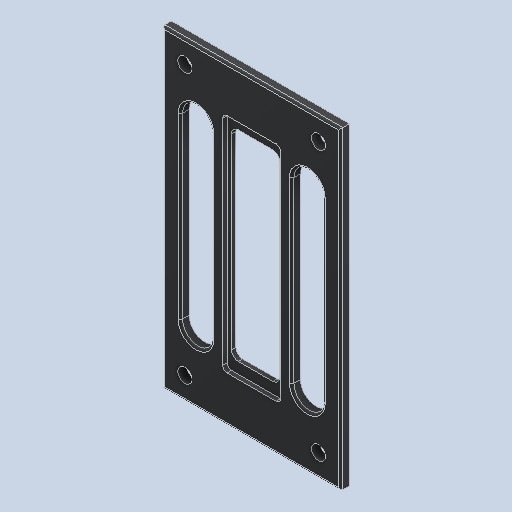
# Autodesk Inventor part: Cabezal camara
Saved by Autodesk Inventor 2025.3 (Build 293356000, 356)
## iProperties
Created: 2026-11-25
Part Number: Cabezal camara
Material: PLA (ácido poliláctico) - FDM nominal
Document SubType Name: Modeling
Designer: STEVEN LONDOÑO
Density: 1.24 g/cm^3
Appearance: PLA negro mate - capas FDM
Author: STEVEN LONDOÑO
Autodesk Inventor part; units mm, degrees
ref_plane "YZ Plane" through (0, 0, 0) normal (1, 0, 0) x (0, 1, 0)
ref_plane "XZ Plane" through (0, 0, 0) normal (0, 1, 0) x (-1, 0, 0)
ref_plane "XY Plane" through (0, 0, 0) normal (0, 0, 1) x (1, 0, 0)
sketch "Boceto1" plane through (0, 0, 0) normal (0, 0, 1) x (1, 0, 0)
  line L0 (-40, 70.44) -> (-40, -70.44)
  line L1 (-40, -70.44) -> (40, -70.44)
  line L2 (40, -70.44) -> (40, 70.44)
  line L3 (40, 70.44) -> (-40, 70.44)
  line L4 (-13.015, 48) -> (-13.015, -48)
  line L5 (-11.015, -50) -> (11.015, -50)
  line L6 (13.015, -48) -> (13.015, 48)
  line L7 (11.015, 50) -> (-11.015, 50)
  arc A0 (-11.015, 50) -> (-13.015, 48) centre (-11.015, 48) ccw
  arc A1 (13.015, 48) -> (11.015, 50) centre (11.015, 48) ccw
  arc A2 (11.015, -50) -> (13.015, -48) centre (11.015, -48) ccw
  arc A3 (-13.015, -48) -> (-11.015, -50) centre (-11.015, -48) ccw
  line L8 (-8, 45) -> (7.537, 45)
  line L9 (10.537, 42) -> (10.537, -42)
  line L10 (7.537, -45) -> (-8, -45)
  line L11 (-11, -42) -> (-11, 42)
  line L12 (-40, 70.44) -> (-20, 70.44)
  line L13 (40, 70.44) -> (20, 70.44)
  circle A4 centre (30, 60.44) radius 3.155
  circle A5 centre (30, -60.44) radius 3.155
  circle A6 centre (-30, 60.44) radius 3.155
  circle A7 centre (-30, -60.44) radius 3.155
  line L14 (-40, 0) -> (-25, 0)
  line L15 (-25, -40) -> (-25, 40) construction
  line L16 (-18, -40) -> (-18, 40)
  line L17 (-32, 40) -> (-32, -40)
  arc A8 (-32, -40) -> (-18, -40) centre (-25, -40) ccw
  arc A9 (-18, 40) -> (-32, 40) centre (-25, 40) ccw
  arc A10 (-8, 45) -> (-11, 42) centre (-8, 42) ccw
  arc A11 (10.537, 42) -> (7.537, 45) centre (7.537, 42) ccw
  arc A12 (-11, -42) -> (-8, -45) centre (-8, -42) ccw
  arc A13 (7.537, -45) -> (10.537, -42) centre (7.537, -42) ccw
  line L18 (40, 0) -> (25, 0)
  line L19 (25, -40) -> (25, 40) construction
  line L20 (32, -40) -> (32, 40)
  line L21 (18, 40) -> (18, -40)
  arc A14 (18, -40) -> (32, -40) centre (25, -40) ccw
  arc A15 (32, 40) -> (18, 40) centre (25, 40) ccw
  point P0 (0, 0)
  point P1 (0, 70.44)
  point P2 (13.015, 0)
  point P3 (0, -45.071)
  point P4 (0, -50)
  point P5 (13.015, 0)
  point P6 (11.25, 0)
  point P7 (0, 45)
  point P8 (-11, 0)
  dimension "d1" = 80
  dimension "d5" = 140.88
  dimension "d18" = 20
  dimension "d26" = 6.31
  dimension "d35" = 15
  dimension "d36" = 40
  dimension "d37" = 14
  constraints: 48 end point, 24 point on circle, 22 tangent, 16 centre point, 9 midpoint, 7 perpendicular, 5 horizontal alignment, 5 parallel, 3 horizontal, 3 point on line, 3 vertical, 3 vertical alignment
  measures "d1" distance of L0.end L1.end
  measures "d5" distance of L0.start L0.end
  measures "d18" distance of L0.start L12.end
  measures "d26" diameter of A7
  measures "d35" distance of L18.start L18.end
  measures "d36" distance of L18.end L19.end
  measures "d37" diameter of A15
extrude "Extrusión1" add sketch "Boceto1" along normal blind 3.95 contours L3 L2 L1 L0
extrude "Extrusión2" add sketch "Boceto1" along normal blind 1.95 contours A0 L7 A1 L6 A2 L5 A3 L4
fillet "Empalme1" radius 1 12 edges at (0, 70.44, 3.95) (0, -70.44, 3.95) (-40, 0, 3.95) (40, 0, 3.95) (25, -47, 3.95) (18, 0, 3.95) (25, 47, 3.95) (32, 0, 3.95) (-25, -47, 3.95) (-32, 0, 3.95) (-25, 47, 3.95) (-18, 0, 3.95)
